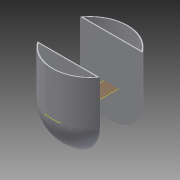
# Autodesk Inventor part: Ball_arm
Saved by Autodesk Inventor 2013 (Build 170138000, 138)
## iProperties
Created: 2013-10-01
Part Number: Ball_arm
Material: Generic
Document SubType Name: Modeling
Designer: Jeff
Density: 1 g/cm^3
Author: Jeff
Autodesk Inventor part; units mm, degrees
ref_plane "YZ Plane" through (0, 0, 0) normal (1, 0, 0) x (0, 1, 0)
ref_plane "XZ Plane" through (0, 0, 0) normal (0, 1, 0) x (-1, 0, 0)
ref_plane "XY Plane" through (0, 0, 0) normal (0, 0, 1) x (1, 0, 0)
ref_plane "Work Plane1" through (0, 0, 0) normal (0, 0, 1) x (1, 0, 0)
sketch "Sketch1" plane through (0, 0, 0) normal (0, 0, 1) x (1, 0, 0)
  line L0 (-41.725, 39.5438) -> (0, 39.5438)
  line L1 (0, 0) -> (-59.9757, 0)
  line L2 (0, 39.5438) -> (57.7606, 39.5438)
  line L3 (0, -39.5438) -> (57.7606, -39.5438)
  line L4 (0, 37.5438) -> (58.3705, 37.5438)
  line L5 (0, -37.5438) -> (58.3705, -37.5438)
  arc A0 (0, -70) -> (57.7606, -39.5438) centre (0, 0) ccw
  arc A1 (58.3705, -37.5438) -> (58.3705, 37.5438) centre (0, 0) ccw
  arc A2 (57.7606, 39.5438) -> (0, 70) centre (0, 0) ccw
  line L6 (0, 0) -> (0, -31.169)
  line L7 (0, -35.5438) -> (57.2685, -35.5438)
  arc A3 (57.2685, -35.5438) -> (57.2685, 35.5438) centre (0, 0) ccw
  line L8 (57.2685, 35.5438) -> (0, 35.5438)
  line L9 (53.8342, 41.5438) -> (0, 41.5438)
  arc A4 (53.8342, 41.5438) -> (0, 68) centre (0, 0) ccw
  line L10 (53.8342, -41.5438) -> (0, -41.5438)
  arc A5 (0, -68) -> (53.8342, -41.5438) centre (0, 0) ccw
  line L11 (0, 39.5438) -> (0, 41.5438)
  line L12 (0, 68) -> (0, 70)
  line L13 (0, 35.5438) -> (0, 37.5438)
  line L14 (0, -70) -> (0, -68)
  line L15 (0, -41.5438) -> (0, -39.5438)
  line L16 (0, -37.5438) -> (0, -35.5438)
  point P0 (0, 0)
  dimension "d0" = 2
  dimension "d1" = 2
  dimension "d2" = 2
  dimension "d3" = 2
  dimension "d4" = 2
  dimension "d5" = 2
  dimension "d6" = 2
  dimension "d7" = 2
  constraints: 32 end point, 12 point on circle, 6 centre point, 2 horizontal, 2 parallel, 1 coincident, 1 symmetric about line, 1 vertical, 2 other
  measures "d0" distance between parallel lines of L4 L2
  measures "d1" radial gap between concentric circles of A1 A3
  measures "d2" distance between parallel lines of L8 L4
  measures "d3" distance between parallel lines of L5 L7
  measures "d4" radial gap between concentric circles of A2 A4
  measures "d5" distance between parallel lines of L2 L9
  measures "d6" distance between parallel lines of L3 L10
  measures "d7" radial gap between concentric circles of A0 A5
revolve "Revolution1" add sketch "Sketch1" angle 180 about axis through (0, 0, 0) along (0, 1, 0) contours L11 L9 A4 L12 A2 L2 | L3 A0 L14 A5 L10 L15
sketch "Sketch2" plane through (0, 0, 0) normal (0, 0, 1) x (1, 0, 0)
  arc A0 (53.8342, 41.5438) -> (-53.8342, 41.5438) centre (0, 0) ccw projected
  line L0 (53.8342, 41.5438) -> (-53.8342, 41.5438) projected
  arc A1 (57.7606, 39.5438) -> (-57.7606, 39.5438) centre (0, 0) ccw projected
  line L1 (-57.7606, 39.5438) -> (57.7606, 39.5438) projected
  arc A2 (-53.8342, -41.5438) -> (53.8342, -41.5438) centre (0, 0) ccw projected
  line L2 (53.8342, -41.5438) -> (-53.8342, -41.5438) projected
  arc A3 (-57.7606, -39.5438) -> (57.7606, -39.5438) centre (0, 0) ccw projected
  line L3 (-57.7606, -39.5438) -> (57.7606, -39.5438) projected
  point P0 (0, -70)
  point P1 (0, 70)
extrude "Extrusion1" add sketch "Sketch2" along normal blind 80
equation "\"d1\" = d8"
equation "\"d2\" = d8"
equation "\"d3\" = d8"
equation "\"d8\" = 2"
body "Solid1"
